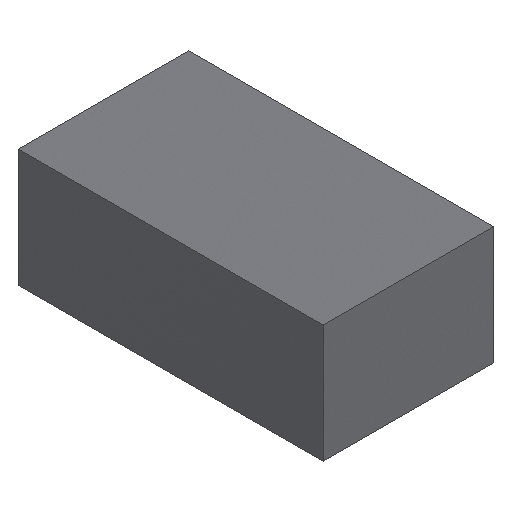
# Autodesk Inventor part: Carcaza
Saved by Autodesk Inventor 2027.1 (Build 311270010, 270A)
## iProperties
Created: 2026-11-17
Part Number: Carcaza
Material: Generic
Document SubType Name: Modeling
Designer: migue
Density: 1 g/cm^3
Appearance: Default
Author: migue
Autodesk Inventor part; units mm, degrees
ref_plane "YZ Plane" through (0, 0, 0) normal (1, 0, 0) x (0, 1, 0)
ref_plane "XZ Plane" through (0, 0, 0) normal (0, 1, 0) x (-1, 0, 0)
ref_plane "XY Plane" through (0, 0, 0) normal (0, 0, 1) x (1, 0, 0)
sketch "Sketch1" plane through (0, 0, 0) normal (0, 1, 0) x (-1, 0, 0)
  line L0 (0, 0) -> (465, 0)
  line L1 (465, 0) -> (465, -260)
  line L2 (465, -260) -> (0, -260)
  line L3 (0, -260) -> (0, 0)
  dimension "d0" = 465
  dimension "d1" = 260
  constraints: 8 end point, 2 parallel, 1 horizontal, 1 perpendicular
  measures "d0" distance of L1.end L2.end
  measures "d1" distance of L2.end L0.start
extrude "Extrusion1" add sketch "Sketch1" along normal blind 180
shell "Shell1" thickness 3 removed faces 1 at (0, 60, -86.6667)
sketch "Sketch2" plane through (-462, 3, -257) normal (0, 1, 0) x (1, 0, 0)
  line L0 (459, -257) -> (459, 3.8806)
  line L1 (462, -257) -> (462, 3) projected
  line L2 (462, 0) -> (462, -254) projected
  line L3 (0, -254) -> (462, -254) projected
  line L4 (462, 0) -> (0, 0) projected
  point P0 (459, 0)
  point P1 (459, -254)
  dimension "d5" = 3
  constraints: 2 end point, 1 vertical
  measures "d5" distance between parallel lines of L1 L0
extrude "Extrusion2" add sketch "Sketch2" along normal blind 176.25
body "Solid1"
